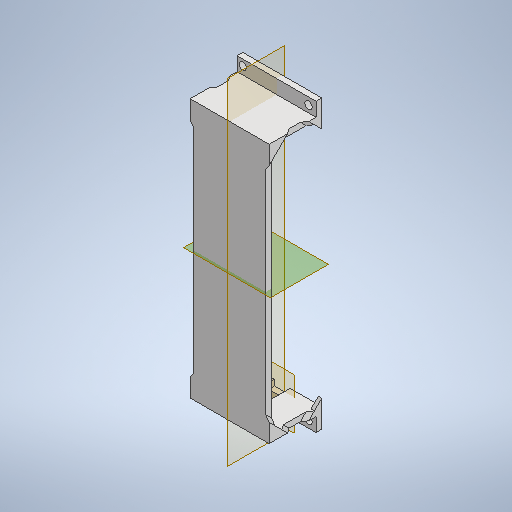
# Autodesk Inventor part: anker_usb_hub_clamp
Saved by Autodesk Inventor 2025.1 (Build 291241000, 241)
## iProperties
Created: 2026-10-19
Part Number: anker_usb_hub_clamp
Material: Generic
Document SubType Name: Modeling
Designer: Aiden Shaevitz
Density: 1 g/cm^3
Appearance: Default
Author: Aiden Shaevitz
Autodesk Inventor part; units mm, degrees
ref_plane "YZ Plane" through (0, 0, 0) normal (1, 0, 0) x (0, 1, 0)
sketch "Sketch1" plane through (0, 0, 0) normal (0, 0, 1) x (1, 0, 0)
  line L0 (-15.621, 53.721) -> (-15.621, -53.721) projected
  line L1 (-15.621, -53.721) -> (15.621, -53.721) projected
  line L2 (15.621, -53.721) -> (15.621, 53.721) projected
  line L3 (15.621, 53.721) -> (-15.621, 53.721) projected
  line L4 (1.905, -53.721) -> (1.905, -66.421)
  line L5 (-1.905, -53.721) -> (-1.905, -66.421)
  line L6 (15.621, 53.721) -> (-15.621, 53.721)
  line L7 (-15.621, 53.721) -> (-15.621, -53.721)
  line L8 (-15.621, -53.721) -> (15.621, -53.721)
  line L9 (15.621, -53.721) -> (15.621, 53.721)
  line L10 (15.621, 53.721) -> (-15.621, -53.721) construction
  line L11 (-15.621, 53.721) -> (15.621, -53.721) construction
  point P0 (0, 0)
  point P1 (0, -53.721)
  point P2 (15.621, 53.721)
  point P3 (-15.621, 53.721)
  point P4 (-8.75, -53.721)
  constraints: 16 end point, 4 midpoint, 2 parallel, 2 vertical, 1 horizontal, 1 perpendicular, 4 other
extrude "Extrusion1" add sketch "Sketch1" along normal blind 2.5
sketch "Sketch2" plane through (0, 0, 2.5) normal (0, 0, 1) x (1, 0, 0)
  line L0 (15.621, 53.721) -> (-15.621, 53.721) projected
  line L1 (-15.621, -53.721) -> (15.621, -53.721) projected
  line L2 (-15.621, -53.721) -> (15.621, -53.721)
  line L3 (15.621, -53.721) -> (15.621, -56.221)
  line L4 (15.621, -56.221) -> (-15.621, -56.221)
  line L5 (-15.621, -56.221) -> (-15.621, -53.721)
  line L6 (-15.621, 53.721) -> (15.621, 53.721)
  line L7 (15.621, 53.721) -> (15.621, 56.221)
  line L8 (15.621, 56.221) -> (-15.621, 56.221)
  line L9 (-15.621, 56.221) -> (-15.621, 53.721)
  line L10 (-15.621, 53.721) -> (-15.621, -53.721) projected
  line L11 (15.621, -53.721) -> (15.621, 53.721) projected
  line L12 (15.621, -53.721) -> (15.621, 53.721) projected
  point P0 (0, 0)
  point P1 (1.905, -53.721)
  point P2 (-1.905, -53.721)
  point P3 (15.621, 53.721)
  point P4 (-8.75, -53.721)
  point P5 (15.621, 53.721)
  point P6 (-15.621, 53.721)
  point P7 (15.621, -54.971)
  point P8 (15.621, 0)
  point P9 (15.621, 54.971)
  point P10 (15.621, 0)
  point P11 (0, 53.721)
  dimension "d4" = 2.5
  dimension "d11" = 2.5
  constraints: 16 end point, 6 midpoint, 4 parallel, 3 vertical alignment, 2 horizontal, 2 perpendicular, 2 other
  measures "d4" distance of L1.start L4.end
  measures "d11" distance of L8.end L6.start
ref_plane "Work Plane1" through (-280.8138, -218.7273, -20.32) normal (0, 0, 1) x (1, 0, 0)
extrude "Extrusion2" add sketch "Sketch2" against normal up to surface (22.82 mm away) contours L0 L9 L8 L7 | L3 L4 L5 L1
ref_plane "Work Plane2" through (-15.6721, -53.721, -10.3173) normal (0, -1, 0) x (1, 0, 0)
sketch "Sketch3" plane through (-15.621, -56.221, 2.5) normal (0, -1, 0) x (1, 0, 0)
  circle A0 centre (15.621, -7.58) radius 1.905 projected
  line L0 (31.242, -22.82) -> (0, -22.82) projected
  line L1 (11.655, -22.82) -> (5.845, -22.82)
  circle A1 centre (15.621, -7.58) radius 1.905 projected
  arc A2 (19.026, -7.58) -> (12.216, -7.58) centre (15.621, -7.58) ccw
  line L2 (12.216, -7.58) -> (12.216, -22.82)
  line L3 (19.026, -7.58) -> (19.026, -22.82)
  line L4 (12.216, -22.82) -> (19.026, -22.82)
  point P0 (15.621, -2.5)
  dimension "d18" = 1.5
  constraints: 8 end point, 4 point on line, 2 collinear, 2 horizontal alignment, 2 perpendicular, 2 point on circle, 1 centre point, 1 coincident
  measures "d18" radial gap between concentric circles of A2 A1
extrude "Extrusion3" cut sketch "Sketch3" against normal up to surface (2.5 mm away) contours A0 | L0 L2 A2 L3
sketch "Sketch6" plane through (15.621, -56.221, 2.5) normal (1, 0, 0) x (0, 0, -1)
  line L0 (4.6925, 37.7574) -> (4.6925, 50.7344) construction
  line L1 (4.6925, 50.7344) -> (10.4675, 50.7344) construction
  line L2 (10.4675, 50.7344) -> (10.4675, 37.7574) construction
  line L3 (10.4675, 37.7574) -> (4.6925, 37.7574) construction
  line L4 (4.6925, 104.4554) -> (10.4675, 104.4554) construction
  line L5 (10.4675, 104.4554) -> (10.4675, 91.4784) construction
  line L6 (10.4675, 91.4784) -> (4.6925, 91.4784) construction
  line L7 (4.6925, 91.4784) -> (4.6925, 104.4554) construction
  line L8 (10.4675, 7.9866) -> (4.6925, 7.9866) construction
  line L9 (4.6925, 7.9866) -> (4.6925, 20.9636) construction
  line L10 (4.6925, 20.9636) -> (10.4675, 20.9636) construction
  line L11 (10.4675, 20.9636) -> (10.4675, 7.9866) construction
  line L12 (10.4675, 74.6846) -> (10.4675, 61.7076) construction
  line L13 (10.4675, 61.7076) -> (4.6925, 61.7076) construction
  line L14 (4.6925, 61.7076) -> (4.6925, 74.6846) construction
  line L15 (4.6925, 74.6846) -> (10.4675, 74.6846) construction
  line L16 (12.66, 2.5) -> (12.66, 109.942) construction
  line L17 (12.66, 109.942) -> (2.5, 109.942) construction
  line L18 (2.5, 2.5) -> (2.5, 109.942) construction
  line L19 (12.66, 2.5) -> (2.5, 2.5) construction
  line L20 (0, 0) -> (22.82, 0) construction
  line L21 (0, 0) -> (0, 112.442) construction
  line L22 (14.8525, 37.7574) -> (14.8525, 50.7344) construction
  line L23 (14.8525, 50.7344) -> (20.6275, 50.7344) construction
  line L24 (20.6275, 50.7344) -> (20.6275, 37.7574) construction
  line L25 (20.6275, 37.7574) -> (14.8525, 37.7574) construction
  line L26 (14.8525, 104.4554) -> (20.6275, 104.4554) construction
  line L27 (20.6275, 104.4554) -> (20.6275, 91.4784) construction
  line L28 (20.6275, 91.4784) -> (14.8525, 91.4784) construction
  line L29 (14.8525, 91.4784) -> (14.8525, 104.4554) construction
  line L30 (20.6275, 7.9866) -> (14.8525, 7.9866) construction
  line L31 (14.8525, 7.9866) -> (14.8525, 20.9636) construction
  line L32 (14.8525, 20.9636) -> (20.6275, 20.9636) construction
  line L33 (20.6275, 20.9636) -> (20.6275, 7.9866) construction
  line L34 (20.6275, 74.6846) -> (20.6275, 61.7076) construction
  line L35 (20.6275, 61.7076) -> (14.8525, 61.7076) construction
  line L36 (14.8525, 61.7076) -> (14.8525, 74.6846) construction
  line L37 (14.8525, 74.6846) -> (20.6275, 74.6846) construction
  line L38 (22.82, 2.5) -> (22.82, 109.942) construction
  line L39 (22.82, 109.942) -> (12.66, 109.942) construction
  line L40 (12.66, 2.5) -> (12.66, 109.942) construction
  line L41 (22.82, 2.5) -> (12.66, 2.5) construction
  line L42 (2.5, 56.221) -> (22.82, 56.221) construction
  line L43 (0, 8) -> (8, 0)
  line L44 (0, 0) -> (0, 8)
  line L45 (7.58, 0) -> (7.58, 2.5) projected
  line L46 (0, 0) -> (8, 0)
  line L47 (10.16, 0) -> (10.16, 112.442) construction
  line L48 (0, 112.442) -> (22.82, 112.442) projected
  line L49 (0, 112.442) -> (20.32, 112.442) construction
  line L50 (0, 112.442) -> (0, 0) construction
  line L51 (0, 104.442) -> (8, 112.442)
  line L52 (0, 112.442) -> (0, 104.442)
  line L53 (0, 112.442) -> (8, 112.442)
  line L54 (22.82, 0) -> (22.82, 2.5) projected
  line L55 (22.82, 0) -> (22.82, 5.6569)
  line L56 (22.82, 5.6569) -> (17.1631, 0)
  line L57 (22.82, 0) -> (17.1631, 0)
  line L58 (22.82, 112.442) -> (22.82, 106.7851)
  line L59 (22.82, 106.7851) -> (17.1631, 112.442)
  line L60 (22.82, 112.442) -> (17.1631, 112.442)
  point P0 (20.32, 0)
  point P1 (22.82, -10)
  point P2 (19.9916, 2.8284)
  point P3 (19.9916, 109.6136)
  point P4 (17.1631, 112.442)
  point P5 (22.82, 2.5)
  dimension "d19" = 8
  dimension "d20" = 8
  dimension "d21" = 4
  constraints: 33 end point, 8 point on line, 8 symmetric about line, 2 midpoint, 2 perpendicular, 1 collinear, 1 parallel
  measures "d19" distance of L20.start L43.start
  measures "d20" distance of L20.start L43.end
  measures "d21" distance of L20.end point (19.992, 2.828)
extrude "Extrusion6" add sketch "Sketch6" along normal blind 1.5
chamfer "Chamfer2" distance 1.5 angle 45 6 edges at (15.621, 54.971, -4.25) (15.621, 54.971, -15.9131) (15.621, -54.971, -15.9131) (15.621, -54.971, -4.25) (15.621, -49.471, 1.25) (15.621, 49.471, 1.25)
ref_plane "Work Plane3" through (0, -50.721, 0) normal (1, 0, 0) x (0, 0, -1)
mirror "Mirror1" about plane through (0, -50.721, 0) normal (1, 0, 0) of "Extrusion6"
chamfer "Chamfer3" distance 1.5 angle 45 6 edges at (-15.621, 54.971, -4.25) (-15.621, 54.971, -15.9131) (-15.621, 49.471, 1.25) (-15.621, -49.471, 1.25) (-15.621, -54.971, -4.25) (-15.621, -54.971, -15.9131)
ref_plane "Work Plane5" through (-3.405, -56.221, -17.82) normal (0, 0, 1) x (1, 0, 0)
sketch "Sketch7" plane through (-3.405, -56.221, -17.82) normal (0, 0, 1) x (1, 0, 0)
  line L0 (-12.216, 0) -> (-12.216, -10) projected
  line L1 (-12.216, -5) -> (19.026, -5) construction
  line L2 (19.026, 0) -> (19.026, -10) projected
  line L3 (-12.216, -10) -> (19.026, -10) projected
  line L4 (3.405, -10) -> (3.405, 0) construction
  line L5 (-13.716, 0) -> (20.526, 0) projected
  line L6 (-12.216, 104.8207) -> (-12.216, 7.6213) projected
  line L7 (19.026, 7.6213) -> (19.026, 104.8207) projected
  point P0 (3.405, 56.221)
  point P1 (-7.32, -5)
  point P2 (14.13, -5)
  dimension "d41" = 21.45
  constraints: 4 end point, 4 midpoint, 1 point on line, 1 symmetric about line
  measures "d41" distance of point (14.13, -5) point (-7.32, -5)
hole "Hole1" at (-10.725, -61.221, -17.82) at (10.725, -61.221, -17.82) direction (0, 0, -1) diameter 3.1 end through all
ref_plane "Work Plane4" through (0, 0, -5.08) normal (0, -1, 0) x (1, 0, 0)
sketch "Sketch8" plane through (3.405, -56.221, -20.32) normal (0, 0, -1) x (-1, 0, 0)
  line L0 (19.026, 2.5) -> (-12.216, 2.5) projected
  line L1 (-12.216, 109.942) -> (19.026, 109.942) projected
  line L2 (-12.216, 2.5) -> (-12.216, 109.942) projected
  line L3 (19.026, 109.942) -> (19.026, 2.5) projected
  line L4 (20.526, 112.442) -> (-13.716, 112.442) projected
  line L5 (-13.716, 112.442) -> (20.526, 112.442)
  line L6 (20.526, 112.442) -> (20.526, 118.442)
  line L7 (20.526, 118.442) -> (-13.716, 118.442)
  line L8 (-13.716, 118.442) -> (-13.716, 112.442)
  line L9 (20.526, 106.7851) -> (20.526, 112.442) projected
  line L10 (3.405, 109.942) -> (3.405, 118.442) construction
  point P0 (20.526, 115.442)
  point P1 (-10.716, 115.442)
  point P2 (17.526, 115.442)
  dimension "d47" = 3
  dimension "d48" = 3
  dimension "d49" = 3
  constraints: 10 end point, 3 midpoint, 2 parallel, 1 horizontal, 1 perpendicular, 1 symmetric about line, 1 vertical alignment
  measures "d47" distance from line of L4 point (-10.716, 115.442)
  measures "d48" distance from line of L8 point (-10.716, 115.442)
  measures "d49" distance from line of point (-10.716, 115.442) L7
extrude "Extrusion7" add sketch "Sketch8" against normal blind 2.5 contours L4 L8 L7 L6
sketch "Sketch11" plane through (15.621, 50.5641, -20.32) normal (0, 0, -1) x (-1, 0, 0)
  point P0 (15.621, -50.5641)
  point P1 (30.2913, 9.0363)
  point P2 (1.7514, 8.6232)
hole "Hole3" at (-14.6703, 59.6004, -20.32) at (13.8696, 59.1873, -20.32) direction (0, 0, 1) diameter 3.2 end through all
ref_plane "Work Plane6" through (0, 0, -5.08) normal (0, -1, 0) x (1, 0, 0)
mirror "Mirror3" about plane through (0, 0, -5.08) normal (0, -1, 0) of "Extrusion7", "Hole3"
body "Solid1"
